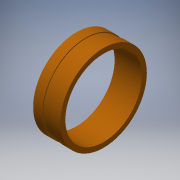
# Autodesk Inventor part: 15-0012-0309
Saved by Autodesk Inventor 2016 SP2 (Build 200236200, 236)
## iProperties
Created: 2017-10-23
Part Number: 15-0012-0309
Material: Plastic (PEEK)
Document SubType Name: Modeling
Designer: jellerm1
Density: 1.32 g/cm^3
Appearance: Orange
User Status: Work in Progress
RuleStatus: InUse
Category: -
Company: Universiteit van Amsterdam
BeforeDocSave0: Open Form
Author: jellerm1
Revision Number: A
Autodesk Inventor part; units mm, degrees
ref_plane "YZ Plane" through (0, 0, 0) normal (1, 0, 0) x (0, 1, 0)
ref_plane "XZ Plane" through (0, 0, 0) normal (0, 1, 0) x (-1, 0, 0)
ref_plane "XY Plane" through (0, 0, 0) normal (0, 0, 1) x (1, 0, 0)
sketch "Sketch1" plane through (0, 0, 0) normal (0, 0, 1) x (1, 0, 0)
  line L0 (0, 86.1045) -> (0, -14.3507) construction
  line L1 (-14.2504, 0) -> (34.5522, 0) construction
  line L2 (0, 22.5) -> (14, 22.5)
  line L3 (14, 22.5) -> (14, 25.4)
  line L4 (14, 25.4) -> (0, 25.4)
  line L5 (0, 25.4) -> (0, 22.5)
  line L6 (0, 0) -> (27.5804, 0)
  line L7 (-7.2786, 23.95) -> (14, 23.95) construction
  line L8 (4.6293, 23.95) -> (-1.2086, 23.95) construction
  arc A0 (0.6638, 25.4) -> (0.6638, 22.5) centre (0.6638, 23.95) ccw construction
  line L9 (0.6638, 23.95) -> (-0.4445, 24.885) construction
  line L10 (5, 26.9) -> (9, 26.9)
  line L11 (9, 26.9) -> (9, 24.9)
  line L12 (9, 24.9) -> (5, 24.9)
  line L13 (5, 24.9) -> (5, 26.9)
  line L14 (7, 26.9) -> (7, 71.7537) construction
  line L15 (7, 25.4) -> (7, 19.6495) construction
  dimension "d0" = 50.8
  dimension "d1" = 45
  dimension "d2" = 90
  dimension "d3" = 0
  dimension "d6" = 1.45
  dimension "d10" = 1.45
  dimension "d11" = 2
  dimension "d12" = 4
  dimension "d13" = 0.5
  dimension "d14" = 5
  dimension "d17" = 90
  dimension "d18" = 7
  constraints: 28 end point, 4 point on line, 3 horizontal, 3 midpoint, 3 parallel, 3 perpendicular, 3 point on circle, 1 centre point, 1 collinear, 1 tangent
  measures "d0" diameter of L4 L6
  measures "d1" diameter of L2 L6
  measures "d2" angle of L2 L5
  measures "d3" distance from line of L0 L2.start
  measures "d6" distance between parallel lines of L7 L2
  measures "d10" distance between parallel lines of L4 L8
  measures "d11" distance of L12.end L10.start
  measures "d12" distance of L10.start L10.end
  measures "d13" distance between parallel lines of L4 L12
  measures "d14" distance from line of L3.end L11
  measures "d17" angle of L2 L3
  measures "d18" distance between parallel lines of L15 L0
revolve "Revolution1" add sketch "Sketch1" angle 360 about axis through (0, 0, 0) along (1, 0, 0) contours L5 L4 L13 L12 L11 L3 L2 | L4 L11 L12 L13
revolve "Revolution2" cut sketch "Sketch1" angle 360 about axis through (0, 0, 0) along (1, 0, 0) contours L13 L10 L11 L4 | L4 L11 L12 L13
equation "\"d10\" = -0.25 * d1 + 0.25 * d0"
body "Solid1"
